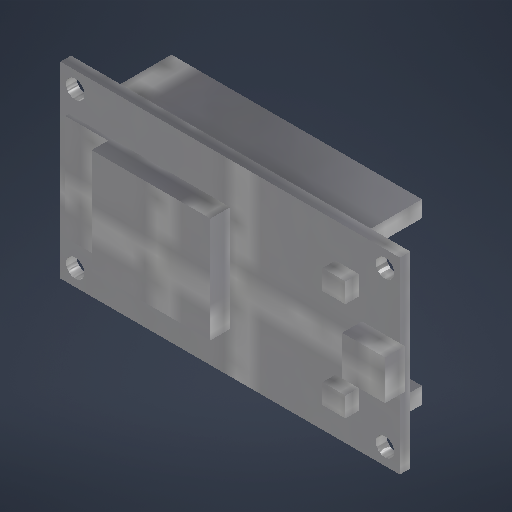
# Autodesk Inventor part: ESP32_DevKit_Module
Saved by Autodesk Inventor 2027.1 (Build 311270010, 270A)
## iProperties
Part Number: ESP32_DevKit_Module
Material: Generic
Document SubType Name: Modeling
Designer: austin
Appearance: Square - Dark Gray
Author: austin
Autodesk Inventor part; units mm, degrees
ref_plane "YZ Plane" through (0, 0, 0) normal (1, 0, 0) x (0, 1, 0)
ref_plane "XZ Plane" through (0, 0, 0) normal (0, 1, 0) x (-1, 0, 0)
sketch "Sketch1" plane through (0, 0, 0) normal (0, 0, 1) x (1, 0, 0)
  line L0 (-25.75, -14.25) -> (25.75, -14.25)
  line L1 (25.75, -14.25) -> (25.75, 14.25)
  line L2 (25.75, 14.25) -> (-25.75, 14.25)
  line L3 (-25.75, 14.25) -> (-25.75, -14.25)
  constraints: 8 end point, 2 parallel, 1 horizontal, 1 perpendicular
extrude "Extrusion1" add sketch "Sketch1" along normal blind 1.6
sketch "Sketch2" plane through (0, 0, 0) normal (0, 0, 1) x (1, 0, 0)
  circle A0 centre (-23.5, -11.75) radius 1.4
  circle A1 centre (23.5, -11.75) radius 1.4
  circle A2 centre (-23.5, 11.75) radius 1.4
  circle A3 centre (23.5, 11.75) radius 1.4
  constraints: 4 centre point
extrude "Extrusion2" cut sketch "Sketch2" along normal blind 2
ref_plane "Work Plane1" through (0, 0, 1.6) normal (0, 0, 1) x (1, 0, 0)
sketch "Sketch3" plane through (0, 0, 1.6) normal (0, 0, 1) x (1, 0, 0)
  line L0 (-18, -8) -> (0, -8)
  line L1 (0, -8) -> (0, 8)
  line L2 (0, 8) -> (-18, 8)
  line L3 (-18, 8) -> (-18, -8)
  constraints: 8 end point, 2 parallel, 1 horizontal, 1 perpendicular
extrude "Extrusion3" add sketch "Sketch3" along normal blind 3
sketch "Sketch4" plane through (0, 0, 1.6) normal (0, 0, 1) x (1, 0, 0)
  line L0 (-24.5, -8) -> (-18, -8)
  line L1 (-18, -8) -> (-18, 8)
  line L2 (-18, 8) -> (-24.5, 8)
  line L3 (-24.5, 8) -> (-24.5, -8)
  constraints: 8 end point, 2 parallel, 1 horizontal, 1 perpendicular
extrude "Extrusion4" add sketch "Sketch4" along normal blind 0.5
sketch "Sketch5" plane through (0, 0, 1.6) normal (0, 0, 1) x (1, 0, 0)
  line L0 (20, -3) -> (26.5, -3)
  line L1 (26.5, -3) -> (26.5, 3)
  line L2 (26.5, 3) -> (20, 3)
  line L3 (20, 3) -> (20, -3)
  constraints: 8 end point, 2 parallel, 1 horizontal, 1 perpendicular
extrude "Extrusion5" add sketch "Sketch5" along normal blind 3
sketch "Sketch6" plane through (0, 0, 0) normal (0, 0, 1) x (1, 0, 0)
  line L0 (-19, -13.5) -> (19, -13.5)
  line L1 (19, -13.5) -> (19, -11)
  line L2 (19, -11) -> (-19, -11)
  line L3 (-19, -11) -> (-19, -13.5)
  line L4 (-19, 11) -> (19, 11)
  line L5 (19, 11) -> (19, 13.5)
  line L6 (19, 13.5) -> (-19, 13.5)
  line L7 (-19, 13.5) -> (-19, 11)
  constraints: 16 end point, 4 parallel, 2 horizontal, 2 perpendicular
extrude "Extrusion6" add sketch "Sketch6" against normal blind 8.5
sketch "Sketch7" plane through (0, 0, 1.6) normal (0, 0, 1) x (1, 0, 0)
  line L0 (16, -9) -> (19.5, -9)
  line L1 (19.5, -9) -> (19.5, -6)
  line L2 (19.5, -6) -> (16, -6)
  line L3 (16, -6) -> (16, -9)
  line L4 (16, 6) -> (19.5, 6)
  line L5 (19.5, 6) -> (19.5, 9)
  line L6 (19.5, 9) -> (16, 9)
  line L7 (16, 9) -> (16, 6)
  constraints: 16 end point, 4 parallel, 2 horizontal, 2 perpendicular
extrude "Extrusion7" add sketch "Sketch7" along normal blind 2
body "Solid1"
